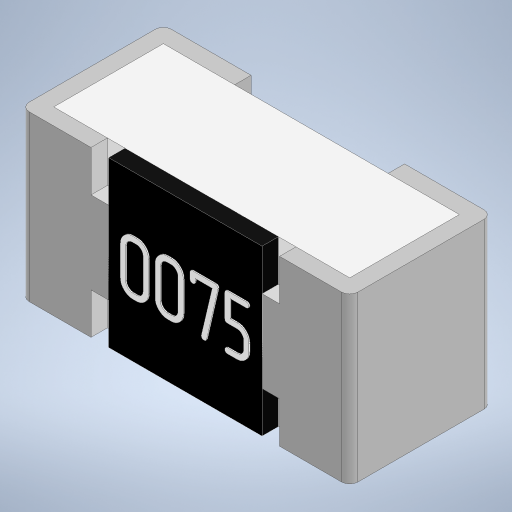
# Autodesk Inventor part: Discrete_Resistors_Ceramic_SMD
Saved by Autodesk Inventor 2024 (Build 280153000, 153)
## iProperties
Created: 2026-11-02
Part Number: Discrete_Resistors_Ceramic_SMD
Material: Generic
Document SubType Name: Modeling
Designer: danil
Density: 1 g/cm^3
Appearance: Default
Author: danil
Autodesk Inventor part; units mm, degrees
ref_plane "YZ Plane" through (0, 0, 0) normal (1, 0, 0) x (0, 1, 0)
ref_plane "XZ Plane" through (0, 0, 0) normal (0, 1, 0) x (-1, 0, 0)
ref_plane "XY Plane" through (0, 0, 0) normal (0, 0, 1) x (1, 0, 0)
sketch "Sketch7" plane through (0, 0, 0) normal (0, 1, 0) x (-1, 0, 0)
  line L0 (0.07, 0) -> (0.15, 0)
  line L1 (0.15, 0) -> (0.15, 0.13)
  line L2 (0.15, 0.13) -> (0.07, 0.13)
  line L3 (0.07, 0.13) -> (0.07, 0.115)
  line L4 (0.07, 0.115) -> (0.135, 0.115)
  line L5 (0.135, 0.115) -> (0.135, 0.015)
  line L6 (0.135, 0.015) -> (0.07, 0.015)
  line L7 (0.07, 0.015) -> (0.07, 0)
  line L8 (0, 0) -> (0, 0.13) construction
  line L9 (0.15, 0.065) -> (0.135, 0.065) construction
  line L10 (-0.07, 0) -> (-0.15, 0)
  line L11 (-0.15, 0) -> (-0.15, 0.13)
  line L12 (-0.15, 0.13) -> (-0.07, 0.13)
  line L13 (-0.07, 0.13) -> (-0.07, 0.115)
  line L14 (-0.07, 0.115) -> (-0.135, 0.115)
  line L15 (-0.135, 0.115) -> (-0.135, 0.015)
  line L16 (-0.135, 0.015) -> (-0.07, 0.015)
  line L17 (-0.07, 0.015) -> (-0.07, 0)
  line L18 (-0.15, 0.065) -> (-0.135, 0.065) construction
  dimension "d22" = 0
  dimension "d24" = 0.015
  dimension "d25" = 0.08
  dimension "d26" = 0.08
  dimension "d27" = 0.13
  dimension "d28" = 0.3
  constraints: 38 end point, 10 symmetric about line, 7 perpendicular, 2 equal length, 2 midpoint, 1 horizontal, 1 horizontal alignment, 1 vertical
  measures "d22" distance from line of L8.start L0
  measures "d24" distance of L6.end L0.start
  measures "d25" distance of L0.start L0.end
  measures "d26" distance of L1.end L2.end
  measures "d27" distance of L0.end L1.end
  measures "d28" distance between parallel lines of L11 L1
extrude "Contacts_extrusion_1" add sketch "Sketch7" along normal mid plane 0.15
sketch "Sketch9" plane through (-0.15, 0.075, 0.13) normal (0, 0, 1) x (1, 0, 0)
  line L0 (0.08, -0.15) -> (0.08, 0) construction
  line L1 (0, 0) -> (0.08, 0) construction
  line L2 (0, -0.15) -> (0, 0) construction
  line L3 (0.08, -0.15) -> (0, -0.15) construction
  line L4 (0.3, -0.15) -> (0.3, 0) construction
  line L5 (0.22, 0) -> (0.3, 0) construction
  line L6 (0.22, -0.15) -> (0.22, 0) construction
  line L7 (0.3, -0.15) -> (0.22, -0.15) construction
  line L8 (0, -0.075) -> (0.3, -0.075) construction
  line L9 (0.15, -0.075) -> (0.15, 0) construction
  line L10 (0.08, 0) -> (0.064, 0)
  line L11 (0.064, 0) -> (0.064, -0.0375)
  line L12 (0.064, -0.0375) -> (0.08, -0.0375)
  line L13 (0.08, -0.0375) -> (0.08, 0)
  line L14 (0.08, -0.15) -> (0.064, -0.15)
  line L15 (0.064, -0.15) -> (0.064, -0.1125)
  line L16 (0.064, -0.1125) -> (0.08, -0.1125)
  line L17 (0.08, -0.1125) -> (0.08, -0.15)
  line L18 (0.22, 0) -> (0.236, 0)
  line L19 (0.236, 0) -> (0.236, -0.0375)
  line L20 (0.236, -0.0375) -> (0.22, -0.0375)
  line L21 (0.22, -0.0375) -> (0.22, 0)
  line L22 (0.22, -0.15) -> (0.236, -0.15)
  line L23 (0.236, -0.15) -> (0.236, -0.1125)
  line L24 (0.236, -0.1125) -> (0.22, -0.1125)
  line L25 (0.22, -0.1125) -> (0.22, -0.15)
  dimension "d33" = 0.0375
  dimension "d34" = 0.016
  constraints: 36 end point, 8 parallel, 4 equal length, 4 horizontal, 4 perpendicular, 2 midpoint, 2 point on line, 1 vertical
  measures "d33" distance of L10.end L11.end
  measures "d34" distance of L11.end L12.end
extrude "Contacts_extrusion_2" cut sketch "Sketch9" against normal up to surface (0.015 mm away)
fillet "Contacts_fillet_1" radius 0.0075 4 edges at (-0.15, 0, 0.13) (0.15, 0, 0.13) (0.15, 0, 0) (-0.15, 0, 0)
sketch "Sketch8" plane through (0, 0, 0) normal (0, 1, 0) x (-1, 0, 0)
  line L0 (0.135, 0.015) -> (0.135, 0.115) projected
  line L1 (0.135, 0.115) -> (-0.135, 0.115)
  line L2 (-0.135, 0.115) -> (-0.135, 0.015)
  line L3 (-0.135, 0.015) -> (0.135, 0.015)
  line L4 (0.135, 0.015) -> (0.135, 0.115)
  point P0 (0, 0)
  constraints: 8 end point, 2 parallel, 1 horizontal, 1 perpendicular
extrude "Ceramic_extrusion_1" add sketch "Sketch8" along normal mid plane 0.15 separate body
sketch "Sketch10" plane through (-0.135, 0.075, 0.115) normal (0, 0, 1) x (1, 0, 0)
  line L0 (0.049, -0.1125) -> (0.065, -0.1125) projected
  line L1 (0.065, -0.1125) -> (0.065, -0.0375) projected
  line L2 (0.065, -0.0375) -> (0.049, -0.0375) projected
  line L3 (0.049, -0.0375) -> (0.049, 0) projected
  line L4 (-0.0075, 0) -> (0.049, 0) projected
  line L5 (0.049, -0.15) -> (-0.0075, -0.15) projected
  line L6 (0.049, -0.15) -> (0.049, -0.1125) projected
  line L7 (0.205, -0.1125) -> (0.221, -0.1125) projected
  line L8 (0.221, -0.1125) -> (0.221, -0.15) projected
  line L9 (0.2775, -0.15) -> (0.221, -0.15) projected
  line L10 (0.221, 0) -> (0.2775, 0) projected
  line L11 (0.221, 0) -> (0.221, -0.0375) projected
  line L12 (0.221, -0.0375) -> (0.205, -0.0375) projected
  line L13 (0.205, -0.1125) -> (0.205, -0.0375) projected
  line L14 (0.065, 0) -> (0.205, 0)
  line L15 (0.205, 0) -> (0.205, -0.15)
  line L16 (0.205, -0.15) -> (0.065, -0.15)
  line L17 (0.065, -0.15) -> (0.065, 0)
  line L18 (0.2775, 0) -> (0.2775, -0.15) projected
  line L19 (-0.0075, -0.15) -> (-0.0075, 0) projected
  point P0 (0.135, -0.075)
  point P1 (0.205, -0.0375)
  constraints: 8 end point, 4 collinear, 2 parallel, 1 horizontal, 1 perpendicular
extrude "Cover_extrusion_1" add sketch "Sketch10" along normal blind 0.015 separate body contours L1 L17 L14 L15 L13 L16
sketch "Sketch11" plane through (-0.135, 0.075, 0.13) normal (0, 0, 1) x (1, 0, 0)
  line L0 (0.065, 0) -> (0.205, 0) construction
  line L1 (0.205, 0) -> (0.205, -0.15) construction
  line L2 (0.205, -0.15) -> (0.065, -0.15) construction
  line L3 (0.065, -0.15) -> (0.065, 0) construction
  line L4 (0.065, 0) -> (0.065, -0.15) construction
  line L5 (0.065, -0.15) -> (0.205, -0.15) construction
  line L6 (0.205, -0.15) -> (0.205, 0) construction
  line L7 (0.205, 0) -> (0.065, 0) construction
  line L8 (0.065, 0) -> (0.065, -0.15) projected
  line L9 (0.205, -0.1125) -> (0.205, -0.0375) projected
  line L10 (0.205, 0) -> (0.065, 0) projected
  spline S0 degree 2 poles (0.1024, -0.0888) (0.1024, -0.0933) (0.0959, -0.0999) (0.0913, -0.0999) knots 0 0 0 1 2 2 2
  line L11 (0.0913, -0.0999) -> (0.0878, -0.0999)
  spline S1 degree 2 poles (0.0878, -0.0999) (0.0836, -0.0999) (0.0767, -0.0934) (0.0767, -0.0888) knots 0 0 0 1 2 2 2
  line L12 (0.0767, -0.0888) -> (0.0767, -0.0612)
  spline S2 degree 2 poles (0.0767, -0.0612) (0.0767, -0.0568) (0.0832, -0.0501) (0.0878, -0.0501) knots 0 0 0 1 2 2 2
  line L13 (0.0878, -0.0501) -> (0.0913, -0.0501)
  spline S3 degree 2 poles (0.0913, -0.0501) (0.0958, -0.0501) (0.1024, -0.0566) (0.1024, -0.0612) knots 0 0 0 1 2 2 2
  line L14 (0.1024, -0.0612) -> (0.1024, -0.0888)
  line L15 (0.0975, -0.0888) -> (0.0975, -0.0612)
  spline S4 degree 2 poles (0.0975, -0.0612) (0.0975, -0.0587) (0.0938, -0.055) (0.0913, -0.055) knots 0 0 0 1 2 2 2
  line L16 (0.0913, -0.055) -> (0.0878, -0.055)
  spline S5 degree 2 poles (0.0878, -0.055) (0.0853, -0.055) (0.0817, -0.0586) (0.0817, -0.0612) knots 0 0 0 1 2 2 2
  line L17 (0.0817, -0.0612) -> (0.0817, -0.0888)
  spline S6 degree 2 poles (0.0817, -0.0888) (0.0817, -0.0913) (0.0854, -0.095) (0.0878, -0.095) knots 0 0 0 1 2 2 2
  line L18 (0.0878, -0.095) -> (0.0913, -0.095)
  spline S7 degree 2 poles (0.0913, -0.095) (0.0938, -0.095) (0.0975, -0.0915) (0.0975, -0.0888) knots 0 0 0 1 2 2 2
  spline S8 degree 2 poles (0.1341, -0.0888) (0.1341, -0.0933) (0.1276, -0.0999) (0.123, -0.0999) knots 0 0 0 1 2 2 2
  line L19 (0.123, -0.0999) -> (0.1195, -0.0999)
  spline S9 degree 2 poles (0.1195, -0.0999) (0.1153, -0.0999) (0.1085, -0.0934) (0.1085, -0.0888) knots 0 0 0 1 2 2 2
  line L20 (0.1085, -0.0888) -> (0.1085, -0.0612)
  spline S10 degree 2 poles (0.1085, -0.0612) (0.1085, -0.0568) (0.1149, -0.0501) (0.1195, -0.0501) knots 0 0 0 1 2 2 2
  line L21 (0.1195, -0.0501) -> (0.123, -0.0501)
  spline S11 degree 2 poles (0.123, -0.0501) (0.1276, -0.0501) (0.1341, -0.0566) (0.1341, -0.0612) knots 0 0 0 1 2 2 2
  line L22 (0.1341, -0.0612) -> (0.1341, -0.0888)
  line L23 (0.1292, -0.0888) -> (0.1292, -0.0612)
  spline S12 degree 2 poles (0.1292, -0.0612) (0.1292, -0.0587) (0.1256, -0.055) (0.123, -0.055) knots 0 0 0 1 2 2 2
  line L24 (0.123, -0.055) -> (0.1195, -0.055)
  spline S13 degree 2 poles (0.1195, -0.055) (0.117, -0.055) (0.1134, -0.0586) (0.1134, -0.0612) knots 0 0 0 1 2 2 2
  line L25 (0.1134, -0.0612) -> (0.1134, -0.0888)
  spline S14 degree 2 poles (0.1134, -0.0888) (0.1134, -0.0913) (0.1171, -0.095) (0.1195, -0.095) knots 0 0 0 1 2 2 2
  line L26 (0.1195, -0.095) -> (0.123, -0.095)
  spline S15 degree 2 poles (0.123, -0.095) (0.1255, -0.095) (0.1292, -0.0915) (0.1292, -0.0888) knots 0 0 0 1 2 2 2
  line L27 (0.1658, -0.0531) -> (0.1554, -0.0979)
  spline S16 degree 2 poles (0.1554, -0.0979) (0.1553, -0.0984) (0.1546, -0.0994) knots 0 0 0 1 1 1
  line L28 (0.1546, -0.0994) -> (0.1532, -0.0999)
  spline S17 degree 2 poles (0.1532, -0.0999) (0.1522, -0.0999) (0.1514, -0.0994) knots 0 0 0 1 1 1
  spline S18 degree 2 poles (0.1514, -0.0994) (0.1505, -0.0986) (0.1505, -0.0974) knots 0 0 0 1 1 1
  line L29 (0.1505, -0.0974) -> (0.1506, -0.0969)
  line L30 (0.1506, -0.0969) -> (0.1605, -0.055)
  line L31 (0.1605, -0.055) -> (0.1451, -0.055)
  line L32 (0.1451, -0.055) -> (0.1451, -0.0577)
  spline S19 degree 2 poles (0.1451, -0.0577) (0.1451, -0.0588) (0.1444, -0.0595) knots 0 0 0 1 1 1
  spline S20 degree 2 poles (0.1444, -0.0595) (0.1437, -0.0602) (0.1427, -0.0602) knots 0 0 0 1 1 1
  spline S21 degree 2 poles (0.1427, -0.0602) (0.1421, -0.0602) (0.141, -0.0597) knots 0 0 0 1 1 1
  spline S22 degree 2 poles (0.141, -0.0597) (0.1402, -0.059) (0.1402, -0.0577) knots 0 0 0 1 1 1
  line L33 (0.1402, -0.0577) -> (0.1402, -0.0526)
  spline S23 degree 2 poles (0.1402, -0.0526) (0.1402, -0.0501) (0.1427, -0.0501) knots 0 0 0 1 1 1
  line L34 (0.1427, -0.0501) -> (0.1634, -0.0501)
  spline S24 degree 2 poles (0.1634, -0.0501) (0.1645, -0.0501) (0.1659, -0.0514) (0.1659, -0.0524) knots 0 0 0 1 2 2 2
  line L35 (0.1659, -0.0524) -> (0.1658, -0.0531)
  spline S25 degree 2 poles (0.1941, -0.0888) (0.1941, -0.0933) (0.1876, -0.0999) (0.183, -0.0999) knots 0 0 0 1 2 2 2
  line L36 (0.183, -0.0999) -> (0.1744, -0.0999)
  spline S26 degree 2 poles (0.1744, -0.0999) (0.1733, -0.0999) (0.1726, -0.0992) knots 0 0 0 1 1 1
  spline S27 degree 2 poles (0.1726, -0.0992) (0.1719, -0.0984) (0.1719, -0.0974) knots 0 0 0 1 1 1
  spline S28 degree 2 poles (0.1719, -0.0974) (0.1719, -0.0968) (0.1731, -0.095) (0.1744, -0.095) knots 0 0 0 1 2 2 2
  line L37 (0.1744, -0.095) -> (0.1831, -0.095)
  spline S29 degree 2 poles (0.1831, -0.095) (0.1856, -0.095) (0.1892, -0.0914) (0.1892, -0.0888) knots 0 0 0 1 2 2 2
  line L38 (0.1892, -0.0888) -> (0.1892, -0.0819)
  spline S30 degree 2 poles (0.1892, -0.0819) (0.1892, -0.0793) (0.1856, -0.0757) (0.1831, -0.0757) knots 0 0 0 1 2 2 2
  line L39 (0.1831, -0.0757) -> (0.1744, -0.0757)
  spline S31 degree 2 poles (0.1744, -0.0757) (0.1719, -0.0757) (0.1719, -0.0732) knots 0 0 0 1 1 1
  line L40 (0.1719, -0.0732) -> (0.1719, -0.0526)
  spline S32 degree 2 poles (0.1719, -0.0526) (0.1719, -0.0501) (0.1744, -0.0501) knots 0 0 0 1 1 1
  line L41 (0.1744, -0.0501) -> (0.1916, -0.0501)
  spline S33 degree 2 poles (0.1916, -0.0501) (0.1926, -0.0501) (0.1941, -0.0516) (0.1941, -0.0525) knots 0 0 0 1 2 2 2
  spline S34 degree 2 poles (0.1941, -0.0525) (0.1941, -0.0534) (0.1928, -0.055) (0.1916, -0.055) knots 0 0 0 1 2 2 2
  line L42 (0.1916, -0.055) -> (0.1768, -0.055)
  line L43 (0.1768, -0.055) -> (0.1768, -0.0708)
  line L44 (0.1768, -0.0708) -> (0.183, -0.0708)
  spline S35 degree 2 poles (0.183, -0.0708) (0.1876, -0.0708) (0.1941, -0.0773) (0.1941, -0.0819) knots 0 0 0 1 2 2 2
  line L45 (0.1941, -0.0819) -> (0.1941, -0.0888)
  point P0 (0.135, -0.075)
  point P1 (0.065, -0.075)
  point P2 (0.065, -0.075)
  point P3 (0.135, 0)
  point P4 (0.135, 0)
  point P5 (0.065, -0.075)
  dimension "d22" = 0
  dimension "d24" = 0.015
  dimension "d25" = 0.08
  dimension "d26" = 0.08
  dimension "d27" = 0.13
  dimension "d28" = 0.3
  constraints: 5 midpoint, 3 coincident, 2 collinear, 2 other
extrude "Text_extrusion_1" add sketch "Sketch11" along normal blind 0.001 separate body
equation "\"vL\" = 0.3"
equation "\"vW\" = 0.15"
equation "\"vH\" = 0.13"
equation "\"vl1\" = 0.08"
equation "\"vl2\" = 0.08"
equation "\"vFont\" = 0.4"
equation "\"vS\" = 0.015"
equation "\"vl1s\" = 0.016"
